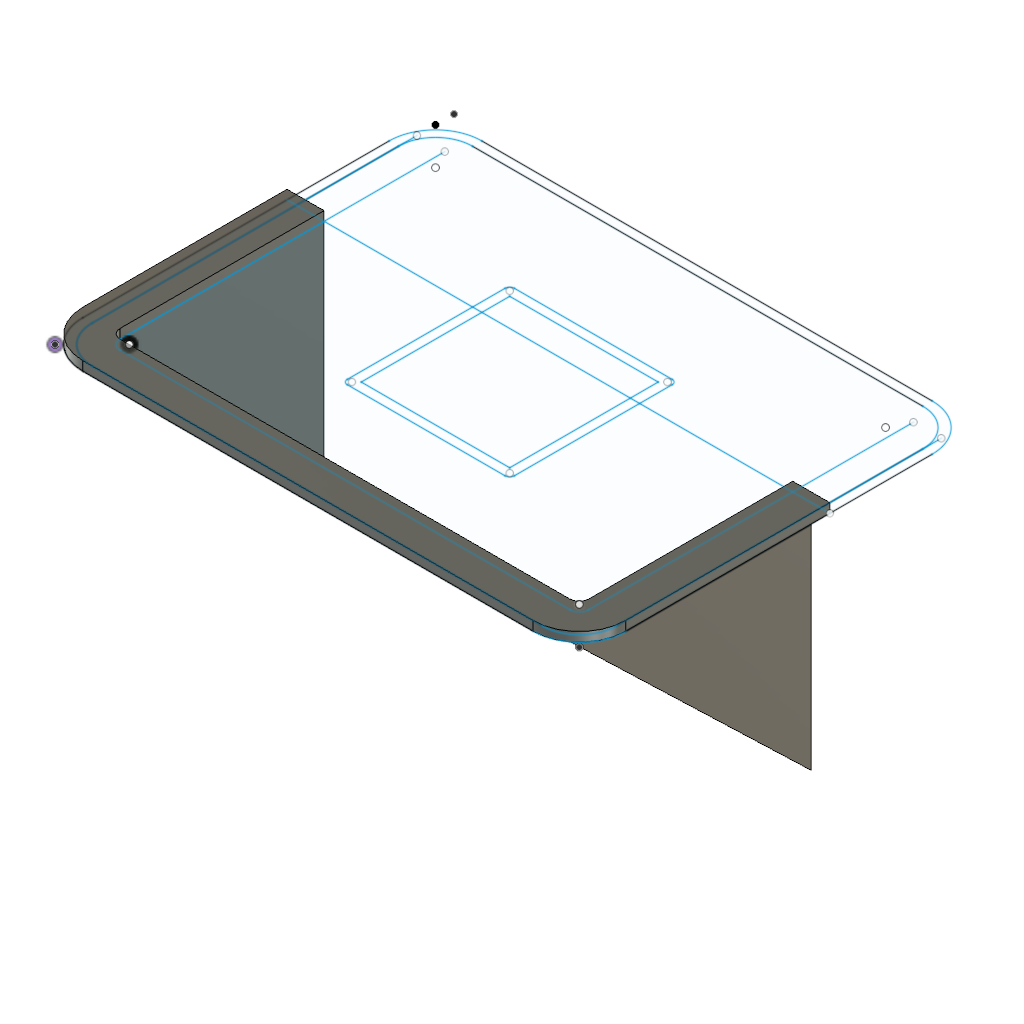
gnss_top_cover (Autodesk Fusion 360 design; units mm, degrees)
Autodesk Fusion 360 part; units mm, degrees
sketch "スケッチ1" plane through (0, 0, 0) normal (0, 0, 1) x (1, 0, 0)
  line L0 (4, 0) -> (52.5, 0)
  line L1 (56.5, 4) -> (56.5, 37)
  line L2 (52.5, 41) -> (4, 41)
  line L3 (0, 37) -> (0, 4)
  arc A0 (0, 4) -> (4, 0) centre (4, 4) ccw
  arc A1 (52.5, 0) -> (56.5, 4) centre (52.5, 4) ccw
  arc A2 (4, 41) -> (0, 37) centre (4, 37) ccw
  arc A3 (56.5, 37) -> (52.5, 41) centre (52.5, 37) ccw
  arc A4 (52.5, 0) -> (56.5, 4) centre (52.5, 4) ccw
  line L4 (4, 0) -> (52.5, 0)
  line L5 (56.5, 4) -> (56.5, 39)
  arc A5 (0, 4) -> (4, 0) centre (4, 4) ccw
  line L6 (0, 39) -> (0, 4)
  line L7 (36, 13) -> (20, 13)
  line L8 (20, 13) -> (20, 29)
  line L9 (20, 29) -> (36, 29)
  line L10 (36, 29) -> (36, 13)
  arc A6 (37, 29.5) -> (36.5, 30) centre (36.5, 29.5) ccw
  line L11 (19.5, 30) -> (36.5, 30)
  arc A7 (19.5, 30) -> (19, 29.5) centre (19.5, 29.5) ccw
  line L12 (19, 12.5) -> (19, 29.5)
  arc A8 (19, 12.5) -> (19.5, 12) centre (19.5, 12.5) ccw
  line L13 (36.5, 12) -> (19.5, 12)
  arc A9 (36.5, 12) -> (37, 12.5) centre (36.5, 12.5) ccw
  line L14 (37, 29.5) -> (37, 12.5)
  line L15 (57.5, 4) -> (57.5, 37)
  arc A10 (57.5, 37) -> (52.5, 42) centre (52.5, 37) ccw
  line L16 (52.5, 42) -> (4, 42)
  arc A11 (4, 42) -> (-1, 37) centre (4, 37) ccw
  line L17 (-1, 37) -> (-1, 4)
  arc A12 (-1, 4) -> (4, -1) centre (4, 4) ccw
  line L18 (4, -1) -> (52.5, -1)
  arc A13 (52.5, -1) -> (57.5, 4) centre (52.5, 4) ccw
  line L19 (3, 39) -> (3, 4)
  arc A14 (3, 4) -> (4, 3) centre (4, 4) ccw
  line L20 (4, 3) -> (52.5, 3)
  arc A15 (52.5, 3) -> (53.5, 4) centre (52.5, 4) ccw
  line L21 (53.5, 4) -> (53.5, 39)
  line L22 (-1, 26) -> (57.5, 26)
  point P0 (56.5, 0)
  point P1 (0, 41)
  point P2 (0, 43)
  point P3 (56.5, 0)
  dimension "d1" = 56.5
  dimension "d2" = 41
  dimension "d3" = 4
  dimension "d4" = 4
  dimension "d5" = 4
  dimension "d6" = 4
  dimension "d7" = 56.5
  dimension "d23" = 16
  dimension "d24" = 16
  dimension "d42" = 1
  dimension "d45" = -3
  constraint horizontal L0
  constraint vertical L1
  constraint horizontal L2
  constraint vertical L3
  constraint coincident origin L3
  constraint coincident origin L0
  constraint tangent L3 A0
  constraint tangent L0 A0
  constraint coincident P3 L0
  constraint coincident P3 L1
  constraint tangent L0 A1
  constraint coincident P1 L2
  constraint coincident P1 L3
  constraint tangent L3 A2
  constraint tangent L1 A3
  constraint horizontal L4
  constraint vertical L5
  constraint vertical L6
  constraint coincident origin L6
  constraint coincident origin L4
  constraint tangent A5 L6
  constraint tangent L4 A5
  constraint coincident P3 L4
  constraint coincident P3 L5
  constraint tangent A4 L4
  constraint coincident P2 L6
  constraint horizontal L7
  constraint vertical L8
  constraint horizontal L9
  constraint vertical L10
  constraint coincident L0.start A5
  constraint perpendicular L15 L22
  constraint coincident L17 L22.start
  measures "d1" distance of origin P3
  measures "d2" distance of origin P1
  measures "d3" radius of A0
  measures "d4" radius of A1
  measures "d5" radius of A2
  measures "d6" radius of A3
  measures "d7" distance of P3 origin
  measures "d23" distance of L7.start L7.end
  measures "d24" distance of L7.start L9.end
extrude "押し出し5" add sketch "スケッチ1" along normal blind 3.5 contours L7 L8 L10 L12 A8 L13 A9 L14 L22 | L8 L9 L10 A6 L11 A7 L12 L14 L22 makes body 1
fillet "フィレット1" radius 0.8 8 edges at (28, 12, 3.5) (36.8536, 12.1464, 3.5) (37, 21, 3.5) (36.8536, 29.8536, 3.5) (28, 30, 3.5) (19.1464, 29.8536, 3.5) (19, 21, 3.5) (19.1464, 12.1464, 3.5) on bodies 1
extrude "押し出し7" add sketch "スケッチ1" along normal blind 0.5 contours L0 L1 L3 A0 A1 A4 L4 L5 A5 L6 L19 A14 L20 A15 L21 L22 | L0 L1 L3 A0 A1 A4 L4 L5 A5 L6 L15 L17 A12 L18 A13 L22 | L1 L2 L3 A2 A3 L5 L6 L15 A10 L16 A11 L17 L22 | L1 L2 L3 A2 A3 L5 L6 A6 L11 A7 L12 L14 L22 | L12 A8 L13 A9 L14 L19 A14 L20 A15 L21 L22 bodies 1
extrude "押し出し8" add sketch "スケッチ1" along normal blind 1 separate body contours L0 L1 L3 A0 A1 A4 L4 L5 A5 L6 L19 A14 L20 A15 L21 L22 | L0 L1 L3 A0 A1 A4 L4 L5 A5 L6 L15 L17 A12 L18 A13 L22 makes body 2
sketch "スケッチ3" plane through (0, 0, 0) normal (1, 0, 0) x (0, 1, 0)
  line L0 (26, 0) -> (0, 0)
  line L1 (0, 0) -> (26, -25)
  line L2 (26, -25) -> (26, 0)
  constraint horizontal L0
  constraint perpendicular L0 L2
extrude "押し出し9" add sketch "スケッチ3" along normal blind 2 separate body makes body 3
copy_body "ボディのコピーと貼り付け1" bodies 3 makes body 4
move_body "移動1" bodies 4 to x (1, 0, 0) y (0, 1, 0) z (0, 0, 1) at (54.5, 0, 0)
move_body "移動2" bodies 3 to x (1, 0, 0) y (0, 1, 0) z (0, 0, 1) at (1, 0, 0)
move_body "移動3" bodies 4 to x (1, 0, 0) y (0, 1, 0) z (0, 0, 1) at (-1, 0, 0)
combine "結合2" operation add target body 2 tool bodies 3 4
hidden bodies 1
